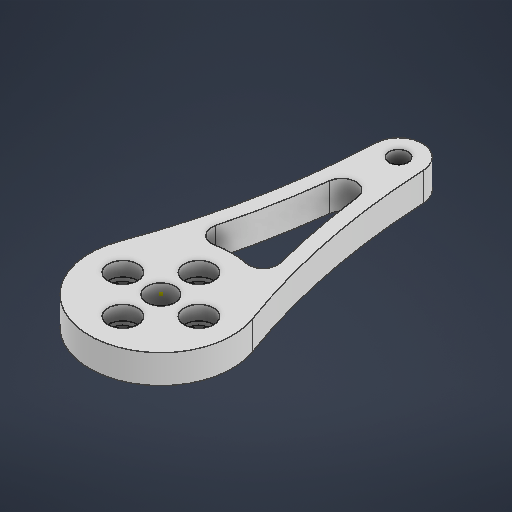
# Autodesk Inventor part: H
Saved by Autodesk Inventor 2026.2 (Build 302298010, 298A)
## iProperties
Created: 2026-03-30
Part Number: H
Material: 일반
Document SubType Name: Modeling
Designer: work
Density: 1 g/cm^3
Appearance: 기본값
Author: work
Autodesk Inventor part; units mm, degrees
ref_plane "YZ Plane" through (0, 0, 0) normal (1, 0, 0) x (0, 1, 0)
ref_plane "XZ Plane" through (0, 0, 0) normal (0, 1, 0) x (-1, 0, 0)
ref_plane "XY Plane" through (0, 0, 0) normal (0, 0, 1) x (1, 0, 0)
sketch "스케치1" plane through (0, 0, 0) normal (0, 1, 0) x (-1, 0, 0)
  circle A0 centre (0, 0) radius 3
  circle A1 centre (8, 0) radius 2
  line L0 (0, 0) -> (8, 0) construction
  circle A2 centre (0, 8) radius 2
  line L1 (0, 0) -> (0, 8) construction
  circle A3 centre (-8, 0) radius 2
  line L2 (0, 0) -> (-8, 0) construction
  circle A4 centre (0, -8) radius 2
  line L3 (0, 0) -> (0, -8) construction
  line L4 (0, 0) -> (0, -50) construction
  circle A5 centre (0, -50) radius 5
  circle A6 centre (0, 0) radius 15
  arc A7 (14.0765, -5.1818) -> (4.9949, -50.2258) centre (154.8419, -57) ccw
  arc A8 (-4.9949, -50.2258) -> (-14.0765, -5.1818) centre (-154.8419, -57) ccw
  arc A9 (11.2612, -4.1455) -> (1.998, -50.0903) centre (154.8419, -57) ccw
  arc A10 (-1.998, -50.0903) -> (-11.2612, -4.1455) centre (-154.8419, -57) ccw
  point P0 (-14.0765, -5.1818)
  point P1 (-4.9949, -50.2258)
  dimension "d8" = 10
  dimension "d9" = 30
  dimension "d0" = 6
  dimension "d1" = 4
  dimension "d2" = 8
  dimension "d5" = 360
  dimension "d7" = 50
  dimension "d10" = 150
  dimension "d11" = 3
  constraints: 10 end point, 9 centre point, 8 point on circle, 6 symmetric about line, 5 coincident, 1 horizontal, 1 point on line, 25 other
  measures "d0" diameter of A0
  measures "d1" diameter of A1
  measures "d2" distance of L0.end point (0, 0)
  measures "d7" distance of L3.start L4.end
  measures "d10" radius of A7
  measures "d11" radial gap between concentric circles of A7 A9
extrude "돌출1" add sketch "스케치1" along normal blind 6
sketch "스케치2" plane through (0, 6, 0) normal (0, 1, 0) x (1, 0, 0)
  point P0 (0, 0)
sketch "스케치3" plane through (0, 6, 0) normal (0, 1, 0) x (1, 0, 0)
  arc A0 (4.9949, 50.2258) -> (14.0765, 5.1818) centre (154.8419, 57) ccw projected
  arc A1 (4.9949, 50.2258) -> (-4.9949, 50.2258) centre (0, 50) ccw projected
  arc A2 (-14.0765, 5.1818) -> (-4.9949, 50.2258) centre (-154.8419, 57) ccw projected
  arc A3 (-14.0765, 5.1818) -> (14.0765, 5.1818) centre (0, 0) ccw projected
  circle A4 centre (0, 8) radius 2 projected
  circle A5 centre (8, 0) radius 2 projected
  circle A6 centre (0, -8) radius 2 projected
  circle A7 centre (-8, 0) radius 2 projected
  circle A8 centre (0, 0) radius 3 projected
  circle A9 centre (0, 0) radius 15
  arc A10 (1.998, 50.0903) -> (-1.998, 50.0903) centre (0, 50) ccw
  arc A11 (1.998, 50.0903) -> (11.2612, 4.1455) centre (154.8419, 57) ccw
  arc A12 (-11.2612, 4.1455) -> (11.2612, 4.1455) centre (0, 0) ccw
  arc A13 (-11.2612, 4.1455) -> (-1.998, 50.0903) centre (-154.8419, 57) ccw
  circle A14 centre (0, 50) radius 5
  point P0 (2.2712, 45.5456)
  point P1 (-2.2712, 45.5456)
  point P2 (-8.4989, 12.36)
  point P3 (8.4989, 12.36)
  dimension "d14" = 3
  constraints: 8 point on circle, 6 centre point, 2 coincident, 2 concentric, 3 other
  measures "d14" radial gap between concentric circles of A2 A13
extrude "돌출2" cut sketch "스케치3" against normal blind 6 contours A9 A13 A14 A11
fillet "모깎기1" radius 3 4 edges at (-8.4989, 3, -12.36) (-2.2712, 3, -45.5456) (2.2712, 3, -45.5456) (8.4989, 3, -12.36)
sketch "스케치4" plane through (0, 6, 0) normal (0, 1, 0) x (1, 0, 0)
  arc A0 (3.2558, 14.6424) -> (-3.2558, 14.6424) centre (0, 0) ccw projected
  arc A1 (-6.8095, 18.3291) -> (-3.2558, 14.6424) centre (-3.907, 17.5709) ccw projected
  arc A2 (-6.8095, 18.3291) -> (-2.9777, 38.3912) centre (-154.8419, 57) ccw projected
  arc A3 (2.9777, 38.3912) -> (-2.9777, 38.3912) centre (0, 38.0263) ccw projected
  arc A4 (2.9777, 38.3912) -> (6.8095, 18.3291) centre (154.8419, 57) ccw projected
  arc A5 (3.2558, 14.6424) -> (6.8095, 18.3291) centre (3.907, 17.5709) ccw projected
  arc A6 (4.9949, 50.2258) -> (14.0765, 5.1818) centre (154.8419, 57) ccw projected
  arc A7 (4.9949, 50.2258) -> (-4.9949, 50.2258) centre (0, 50) ccw projected
  arc A8 (-14.0765, 5.1818) -> (-4.9949, 50.2258) centre (-154.8419, 57) ccw projected
  arc A9 (-14.0765, 5.1818) -> (14.0765, 5.1818) centre (0, 0) ccw projected
  circle A10 centre (0, 8) radius 2 projected
  circle A11 centre (8, 0) radius 2 projected
  circle A12 centre (0, -8) radius 2 projected
  circle A13 centre (-8, 0) radius 2 projected
  circle A14 centre (0, 0) radius 3 projected
  circle A15 centre (0, 50) radius 2
  dimension "d18" = 4
  constraints: 1 centre point, 1 coincident
  measures "d18" diameter of A15
extrude "돌출3" cut sketch "스케치4" against normal blind 6 contours A15
sketch "스케치5" plane through (0, 6, 0) normal (0, 1, 0) x (1, 0, 0)
  circle A0 centre (0, 50) radius 2 projected
  arc A1 (3.2558, 14.6424) -> (-3.2558, 14.6424) centre (0, 0) ccw projected
  arc A2 (-6.8095, 18.3291) -> (-3.2558, 14.6424) centre (-3.907, 17.5709) ccw projected
  arc A3 (-6.8095, 18.3291) -> (-2.9777, 38.3912) centre (-154.8419, 57) ccw projected
  arc A4 (2.9777, 38.3912) -> (-2.9777, 38.3912) centre (0, 38.0263) ccw projected
  arc A5 (2.9777, 38.3912) -> (6.8095, 18.3291) centre (154.8419, 57) ccw projected
  arc A6 (3.2558, 14.6424) -> (6.8095, 18.3291) centre (3.907, 17.5709) ccw projected
  arc A7 (4.9949, 50.2258) -> (14.0765, 5.1818) centre (154.8419, 57) ccw projected
  arc A8 (4.9949, 50.2258) -> (-4.9949, 50.2258) centre (0, 50) ccw projected
  arc A9 (-14.0765, 5.1818) -> (-4.9949, 50.2258) centre (-154.8419, 57) ccw projected
  arc A10 (-14.0765, 5.1818) -> (14.0765, 5.1818) centre (0, 0) ccw projected
  circle A11 centre (0, 8) radius 2 projected
  circle A12 centre (8, 0) radius 2 projected
  circle A13 centre (0, -8) radius 2 projected
  circle A14 centre (-8, 0) radius 2 projected
  circle A15 centre (0, 0) radius 3 projected
  constraints: 4 coincident
hole "구멍1" at (-8, 6, 0) at (0, 6, 8) at (0, 6, -8) at (8, 6, 0) direction (0, -1, 0) diameter 4 end through all counterbore diameter 6.2 counterbore depth 3
sketch "스케치6" plane through (0, 6, 0) normal (0, 1, 0) x (1, 0, 0)
  point P0 (0, 0)
